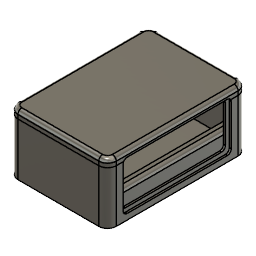
Modulo Servo (4 x6) (Autodesk Fusion 360 design; units mm, degrees)
Autodesk Fusion 360 part; units mm, degrees
sketch "Esboço1" plane through (0, 0, 0) normal (0, 0, 1) x (1, 0, 0)
  line L0 (0, 0) -> (22, 0)
  line L1 (0, 0) -> (0, 10)
  line L2 (0, 10) -> (4, 10)
  line L3 (4, 10) -> (4, 8)
  line L4 (4, 8) -> (2, 8)
  line L5 (2, 8) -> (2, 6)
  line L6 (2, 6) -> (4, 6)
  line L7 (4, 6) -> (4, 4)
  line L8 (4, 4) -> (2, 4)
  line L9 (2, 4) -> (2, 2)
  line L10 (2, 2) -> (22, 2)
  line L11 (22, 2) -> (22, 0)
  line L12 (40, 6) -> (40, 4)
  line L13 (40, 10) -> (40, 8)
  line L14 (44, 10) -> (40, 10)
  line L15 (42, 4) -> (42, 2)
  line L16 (22, 2) -> (22, 0)
  line L17 (42, 2) -> (22, 2)
  line L18 (42, 6) -> (40, 6)
  line L19 (44, 0) -> (22, 0)
  line L20 (40, 8) -> (42, 8)
  line L21 (42, 8) -> (42, 6)
  line L22 (44, 0) -> (44, 10)
  line L23 (40, 4) -> (42, 4)
  point P0 (44, 0)
  dimension "d2" = 10
  dimension "d3" = 4
  dimension "d4" = 2
  dimension "d5" = 2
  dimension "d6" = 2
  dimension "d7" = 2
  dimension "d8" = 2
  dimension "d9" = 2
  dimension "d10" = 2
  dimension "d11" = 20
  constraint coincident L0.start L1.start
  constraint horizontal L0
  constraint perpendicular L0 L1
  constraint perpendicular L1 L2
  constraint perpendicular L2 L3
  constraint perpendicular L1 L4
  constraint perpendicular L4 L5
  constraint perpendicular L5 L6
  constraint perpendicular L6 L7
  constraint perpendicular L7 L8
  constraint perpendicular L0 L9
  constraint perpendicular L9 L10
  constraint symmetric L0.start L11 L19.start
  constraint symmetric L0.start L11 P0
  constraint symmetric L1.end L11 L14.start
  constraint symmetric L2.end L11 L13.start
  constraint symmetric L3.end L11 L13.end
  constraint symmetric L4.end L11 L20.end
  constraint symmetric L5.end L11 L18.start
  constraint symmetric L6.end L11 L12.start
  constraint symmetric L7.end L11 L12.end
  constraint symmetric L8.end L11 L15.start
  constraint symmetric L9.end L11 L15.end
  constraint symmetric L10.end L11 L16.start
  constraint symmetric L0.end L11 L16.end
  measures "d2" distance of L0.start L1.end
  measures "d3" distance of L1.end L2.end
  measures "d4" distance of L2.end L3.end
  measures "d5" distance of L3.end L4.end
  measures "d6" distance of L4.end L5.end
  measures "d7" distance of L5.end L6.end
  measures "d8" distance of L6.end L7.end
  measures "d9" distance of L7.end L8.end
  measures "d10" distance of L8.end L9.end
  measures "d11" distance of L9.end L10.end
sketch "Esboço2" plane through (0, 0, 0) normal (0, 0, 1) x (1, 0, 0)
extrude "Extrusão1" add sketch "Esboço1" along normal blind 65 makes body 1
fillet "Arredondamento1" radius 2 2 edges at (0, 10, 32.5) (44, 10, 32.5) on bodies 1
sketch "Esboço3" plane through (0, 0, 65) normal (0, 0, 1) x (1, 0, 0)
  arc A0 (44, 8) -> (42, 10) centre (42, 8) ccw
  line L0 (42, 10) -> (40, 10)
  line L1 (40, 10) -> (40, 8)
  line L2 (40, 8) -> (42, 8)
  line L3 (42, 8) -> (42, 6)
  line L4 (42, 6) -> (40, 6)
  line L5 (40, 6) -> (40, 4)
  line L6 (40, 4) -> (42, 4)
  line L7 (42, 4) -> (42, 2)
  line L8 (42, 2) -> (2, 2)
  line L9 (2, 2) -> (2, 4)
  line L10 (2, 4) -> (4, 4)
  line L11 (4, 4) -> (4, 6)
  line L12 (4, 6) -> (2, 6)
  line L13 (2, 6) -> (2, 8)
  line L14 (2, 8) -> (4, 8)
  line L15 (4, 8) -> (4, 10)
  line L16 (4, 10) -> (2, 10)
  arc A1 (2, 10) -> (0, 8) centre (2, 8) ccw
  line L17 (0, 8) -> (0, 0)
  line L18 (0, 0) -> (44, 0)
  line L19 (44, 0) -> (44, 8)
  line L20 (2, 8) -> (4, 8)
  line L21 (4, 8) -> (4, 6)
  line L22 (4, 6) -> (2, 6)
  line L23 (2, 6) -> (2, 8)
  line L24 (40, 8) -> (42, 8)
  line L25 (42, 8) -> (42, 6)
  line L26 (42, 6) -> (40, 6)
  line L27 (40, 6) -> (40, 8)
  constraint horizontal L20
  constraint vertical L21
  constraint horizontal L22
  constraint vertical L23
  constraint coincident L11.end L12.start
  constraint coincident L13.end L14.start
  constraint horizontal L24
  constraint vertical L25
  constraint horizontal L26
  constraint vertical L27
  constraint coincident L3.end L4.start
  constraint coincident L1.end L2.start
sketch "Esboço5" plane through (0, 0, 0) normal (0, -1, 0) x (1, 0, 0)
  line L0 (0, 0) -> (44, 0)
  line L1 (44, 0) -> (44, 65)
  line L2 (44, 65) -> (0, 65)
  line L3 (0, 65) -> (0, 0)
  line L4 (0, 0) -> (0, 32.5)
  line L5 (0, 32.5) -> (22, 32.5)
  line L6 (46.5, 67.5) -> (-2.5, 67.5)
  line L7 (-2.5, 67.5) -> (-2.5, -2.5)
  line L8 (-2.5, -2.5) -> (46.5, -2.5)
  line L9 (46.5, -2.5) -> (46.5, 67.5)
  line L10 (46.5, 67.5) -> (-2.5, -2.5) construction
  line L11 (-2.5, 67.5) -> (46.5, -2.5) construction
  line L12 (45, 66) -> (-1, 66)
  line L13 (-1, 66) -> (-1, -1)
  line L14 (-1, -1) -> (45, -1)
  line L15 (45, -1) -> (45, 66)
  line L16 (45, 66) -> (-1, -1) construction
  line L17 (-1, 66) -> (45, -1) construction
  point P0 (22, 32.5)
  point P1 (22, 32.5)
  dimension "d33" = 32.5
  dimension "d34" = 22
  dimension "d35" = 70
  dimension "d36" = 49
  dimension "d37" = 46
  dimension "d38" = 67
  constraint coincident L0.start L3.end
  constraint perpendicular L2 L4
  constraint perpendicular L4 L5
  constraint horizontal L6
  constraint perpendicular L6 L7
  constraint parallel L6 L8
  constraint parallel L7 L9
  constraint coincident L10 P1
  constraint coincident L11 P1
  constraint coincident P1 P0
  constraint horizontal L12
  constraint perpendicular L12 L13
  constraint parallel L12 L14
  constraint parallel L13 L15
  constraint coincident L16 P1
  constraint coincident L17 P1
  measures "d33" distance of L0.start L4.end
  measures "d34" distance of L4.end P1
  measures "d35" distance of L6.end L7.end
  measures "d36" distance of L7.end L8.end
  measures "d37" distance of L13.end L14.end
  measures "d38" distance of L12.end L13.end
copy_body "Corpo -> Componente1" bodies 1 removing the originals makes body 2 in component "Placa 4x6"
sketch "Esboço7" plane through (0, 0, 0) normal (0, -1, 0) x (1, 0, 0)
  line L0 (0, 0) -> (44, 0)
  line L1 (44, 0) -> (44, 65)
  line L2 (44, 65) -> (0, 65)
  line L3 (0, 65) -> (0, 0)
  line L4 (0, 0) -> (0, 32.5)
  line L5 (0, 32.5) -> (22, 32.5)
  line L6 (44.75, -0.75) -> (-0.75, -0.75)
  line L7 (-0.75, -0.75) -> (-0.75, 65.75)
  line L8 (-0.75, 65.75) -> (44.75, 65.75)
  line L9 (44.75, 65.75) -> (44.75, -0.75)
  line L10 (44.75, -0.75) -> (-0.75, 65.75) construction
  line L11 (-0.75, -0.75) -> (44.75, 65.75) construction
  line L12 (42.75, 67.75) -> (1.25, 67.75)
  line L13 (-2.75, 63.75) -> (-2.75, 1.25)
  line L14 (1.25, -2.75) -> (42.75, -2.75)
  line L15 (46.75, 1.25) -> (46.75, 63.75)
  line L16 (46.75, 67.75) -> (-2.75, -2.75) construction
  line L17 (-2.75, 67.75) -> (46.75, -2.75) construction
  arc A0 (1.25, 67.75) -> (-2.75, 63.75) centre (1.25, 63.75) ccw
  arc A1 (46.75, 63.75) -> (42.75, 67.75) centre (42.75, 63.75) ccw
  arc A2 (42.75, -2.75) -> (46.75, 1.25) centre (42.75, 1.25) ccw
  arc A3 (-2.75, 1.25) -> (1.25, -2.75) centre (1.25, 1.25) ccw
  point P0 (22, 32.5)
  point P1 (22, 32.5)
  dimension "d45" = 32.5
  dimension "d46" = 22
  dimension "d47" = 66.5
  dimension "d48" = 45.5
  dimension "d49" = 49.5
  dimension "d50" = 70.5
  dimension "d54" = 4
  constraint coincident L0.start L3.end
  constraint perpendicular L0 L4
  constraint perpendicular L4 L5
  constraint horizontal L6
  constraint perpendicular L6 L7
  constraint parallel L6 L8
  constraint parallel L7 L9
  constraint coincident L10 P1
  constraint coincident L11 P1
  constraint coincident P1 P0
  constraint horizontal L12
  constraint perpendicular L12 L13
  constraint parallel L12 L14
  constraint parallel L13 L15
  constraint coincident L16 P1
  constraint coincident L17 P1
  constraint coincident L17.start L13
  constraint coincident L17.start L12
  constraint tangent L13 A0
  constraint tangent L12 A0
  constraint coincident L16.start L12
  constraint coincident L16.start L15
  constraint tangent L12 A1
  constraint tangent L15 A1
  constraint equal A0 A1
  constraint coincident L17.end L14
  constraint coincident L17.end L15
  constraint tangent L14 A2
  constraint tangent L15 A2
  constraint equal A0 A2
  constraint coincident L16.end L14
  constraint coincident L16.end L13
  constraint tangent L14 A3
  constraint tangent L13 A3
  constraint equal A0 A3
  measures "d45" distance of L0.start L4.end
  measures "d46" distance of L4.end P1
  measures "d47" distance of L6.end L7.end
  measures "d48" distance of L7.end L8.end
  measures "d49" distance of L16.end L17.end
  measures "d50" distance of L17.start L16.end
  measures "d54" radius of A0
extrude "Extrusão8" add sketch "Esboço7" against normal blind 25 thin wall 1 centred separate body contours L12 L13 L14 L15 A0 A1 A2 A3 makes body 3
copy_body "Corpo -> Componente2" bodies 3 removing the originals makes body 4 in component "Suporte Placa (1)"
extrude "Extrusão1'" add sketch "Esboço7" along normal blind 2 contours L0 L1 L2 L3 L4 | L6 L7 L8 L9 | L12 L13 L14 L15 A0 A1 A2 A3 bodies 4 in component "Suporte Placa (1)"
sketch "Esboço1 (2)" plane through (0, 25, 0) normal (0, 1, 0) x (-1, 0, 0) in component "Suporte Placa (1)"
  arc A0 (2.25, 63.75) -> (1.25, 66.1995) centre (-1.25, 63.75) ccw
  line L0 (2.25, 63.75) -> (2.25, 1.25)
  arc A1 (1.25, -1.1995) -> (2.25, 1.25) centre (-1.25, 1.25) ccw
  line L1 (1.25, -1.1995) -> (1.25, 66.1995)
  arc A2 (-42.75, 67.25) -> (-45.1995, 66.25) centre (-42.75, 63.75) ccw
  line L2 (-42.75, 67.25) -> (-1.25, 67.25)
  arc A3 (1.1995, 66.25) -> (-1.25, 67.25) centre (-1.25, 63.75) ccw
  line L3 (1.1995, 66.25) -> (-45.1995, 66.25)
  arc A4 (-1.25, -2.25) -> (1.1995, -1.25) centre (-1.25, 1.25) ccw
  line L4 (-1.25, -2.25) -> (-42.75, -2.25)
  arc A5 (-45.1995, -1.25) -> (-42.75, -2.25) centre (-42.75, 1.25) ccw
  line L5 (-45.1995, -1.25) -> (1.1995, -1.25)
  arc A6 (-46.25, 1.25) -> (-45.25, -1.1995) centre (-42.75, 1.25) ccw
  line L6 (-46.25, 1.25) -> (-46.25, 63.75)
  arc A7 (-45.25, 66.1995) -> (-46.25, 63.75) centre (-42.75, 63.75) ccw
  line L7 (-45.25, 66.1995) -> (-45.25, -1.1995)
  line L8 (-44.25, 65.25) -> (0.25, 65.25)
  line L9 (0.25, 65.25) -> (0.25, -0.25)
  line L10 (0.25, -0.25) -> (-44.25, -0.25)
  line L11 (-44.25, -0.25) -> (-44.25, 65.25)
  arc A8 (-1.25, -3.25) -> (3.25, 1.25) centre (-1.25, 1.25) ccw
  line L12 (3.25, 1.25) -> (3.25, 63.75)
  arc A9 (3.25, 63.75) -> (-1.25, 68.25) centre (-1.25, 63.75) ccw
  line L13 (-1.25, 68.25) -> (-42.75, 68.25)
  arc A10 (-42.75, 68.25) -> (-47.25, 63.75) centre (-42.75, 63.75) ccw
  line L14 (-47.25, 63.75) -> (-47.25, 1.25)
  line L15 (-42.75, -3.25) -> (-1.25, -3.25)
  line L16 (0.25, -0.25) -> (0.25, 1.75)
  line L17 (0.25, -0.25) -> (-1.75, -0.25)
  line L18 (-1.75, -0.25) -> (-1.75, -3.25)
  line L19 (0.25, 1.75) -> (3.25, 1.75)
  line L20 (-42.25, -3.25) -> (-42.75, -3.25)
  line L21 (-47.25, 1.25) -> (-47.25, 1.75)
  line L22 (-22, -3.25) -> (-22, 32.5)
  line L23 (-22, 32.5) -> (3.25, 32.5)
  arc A11 (3.25, 63.75) -> (-1.25, 68.25) centre (-1.25, 63.75) ccw
  line L24 (-1.75, 65.25) -> (-1.75, 68.25)
  line L25 (0.25, 65.25) -> (-1.75, 65.25)
  line L26 (0.25, 63.25) -> (3.25, 63.25)
  line L27 (0.25, 63.25) -> (0.25, 65.25)
  line L28 (-44.25, 1.75) -> (-47.25, 1.75)
  line L29 (-44.25, -0.25) -> (-44.25, 1.75)
  line L30 (-44.25, -0.25) -> (-42.25, -0.25)
  line L31 (-42.25, -0.25) -> (-42.25, -3.25)
  arc A12 (-47.25, 1.25) -> (-42.75, -3.25) centre (-42.75, 1.25) ccw
  line L32 (-44.25, 63.25) -> (-47.25, 63.25)
  line L33 (-44.25, 63.25) -> (-44.25, 65.25)
  line L34 (-44.25, 65.25) -> (-42.25, 65.25)
  line L35 (-42.25, 65.25) -> (-42.25, 68.25)
  arc A13 (-42.75, 68.25) -> (-47.25, 63.75) centre (-42.75, 63.75) ccw
  dimension "d57" = 2
  dimension "d58" = 2
  dimension "d59" = 35.75
  constraint coincident L9.end L10.start
  constraint perpendicular L10 L16
  constraint perpendicular L16 L17
  constraint coincident L15 L18.end
  constraint perpendicular L15 L18
  constraint coincident L12 L19.end
  constraint perpendicular L12 L19
  constraint midpoint L15 L22.start
  constraint perpendicular L10 L22
  constraint midpoint L12 L23.end
  constraint symmetric A8.start L23 A9.end
  constraint symmetric A8.end L23 L12.end
  constraint symmetric A8 L23 A11
  constraint symmetric L16.end L23 L26.start
  constraint symmetric L9.end L23 L8.end
  constraint symmetric L17.end L23 L24.start
  constraint symmetric L18.end L23 L24.end
  constraint symmetric L19.end L23 L26.end
  constraint coincident L8.end L9.start
  constraint symmetric A8.start L22 L15.start
  constraint symmetric A8.end L22 L14.end
  constraint symmetric A8 L22 A12
  constraint symmetric L9.end L22 L10.end
  constraint symmetric L16.end L22 L28.start
  constraint symmetric L17.end L22 L30.end
  constraint symmetric L18.end L22 L20.start
  constraint symmetric L19.end L22 L21.end
  constraint symmetric L22 A9.end L13.end
  constraint symmetric L22 L12.end A10.end
  constraint symmetric L22 A11 A13
  constraint symmetric L22 L24.start L34.end
  constraint symmetric L22 L24.end L35.end
  constraint symmetric L22 L8.end L8.start
  constraint symmetric L22 L26.start L32.start
  constraint symmetric L22 L26.end L32.end
  measures "d57" distance of L9.end L16.end
  measures "d58" distance of L9.end L17.end
  measures "d59" distance of L22.start L22.end
extrude "Extrusão2" add sketch "Esboço1 (2)" against normal blind 25 contours A0 L0 L1 L26 | L0 A1 L1 L19 | L2 A3 L3 L24 | A2 L2 L3 L35 | A4 L4 L5 L18 | L4 A5 L5 L31 | L6 A7 L7 L32 | A6 L6 L7 L28 bodies 4 in component "Suporte Placa (1)"
extrude "Extrusão3" cut sketch "Esboço1 (2)" against normal blind 1.5 contours A0 L0 L1 L26 | L0 A1 L1 L19 | L2 A3 L3 L24 | A2 L2 L3 L35 | A4 L4 L5 L18 | L4 A5 L5 L31 | L6 A7 L7 L32 | A6 L6 L7 L28 bodies 4 in component "Suporte Placa (1)"
extrude "Extrusão4" add 1 faces at (30.25, -2, 22.0833) along direction (0, 1, 0) blind 2 thin wall 1 centred on bodies 4 bodies 4 in component "Suporte Placa (1)"
ref_plane "Plano de trabalho1" through (22, 25, 32.5) normal (0, 1, 0) x (-1, 0, 0) in component "Suporte Placa (1)"
sketch "Esboço3 (2)" plane through (0, 25, 0) normal (0, 1, 0) x (1, 0, 0) in component "Suporte Placa (1)"
extrude "Extrusão7" add 1 faces at (-0.9167, 25, 21.5833) along direction (0, 1, 0) blind 2 separate body on bodies 4 makes body 5 in component "Suporte Placa (1)"
copy_body "CutPasteBodies1" bodies 5 removing the originals makes body 6 in component "Tampa"
sketch "Esboço1 (3)" plane through (0, 27, 0) normal (0, 1, 0) x (-1, 0, 0) in component "Tampa"
  line L0 (-44.25, -0.25) -> (-44.25, 65.25)
  line L1 (-44.25, 65.25) -> (0.25, 65.25)
  line L2 (0.25, 65.25) -> (0.25, -0.25)
  line L3 (0.25, -0.25) -> (-44.25, -0.25)
  line L4 (-45.25, 66.1995) -> (-45.25, -1.1995)
  arc A0 (-46.25, 1.25) -> (-45.25, -1.1995) centre (-42.75, 1.25) ccw
  line L5 (-46.25, 1.25) -> (-46.25, 63.75)
  line L6 (-47.25, 63.75) -> (-47.25, 1.25)
  arc A1 (-47.25, 1.25) -> (-42.75, -3.25) centre (-42.75, 1.25) ccw
  line L7 (-42.75, -3.25) -> (-1.25, -3.25)
  arc A2 (-1.25, -3.25) -> (3.25, 1.25) centre (-1.25, 1.25) ccw
  line L8 (3.25, 1.25) -> (3.25, 63.75)
  arc A3 (3.25, 63.75) -> (-1.25, 68.25) centre (-1.25, 63.75) ccw
  line L9 (-1.25, 68.25) -> (-42.75, 68.25)
  arc A4 (-42.75, 68.25) -> (-47.25, 63.75) centre (-42.75, 63.75) ccw
  arc A5 (-45.25, 66.1995) -> (-46.25, 63.75) centre (-42.75, 63.75) ccw
  line L10 (2.25, 63.75) -> (2.25, 1.25)
  arc A6 (1.25, -1.1995) -> (2.25, 1.25) centre (-1.25, 1.25) ccw
  line L11 (1.25, -1.1995) -> (1.25, 66.1995)
  arc A7 (2.25, 63.75) -> (1.25, 66.1995) centre (-1.25, 63.75) ccw
  line L12 (-42.75, 67.25) -> (-1.25, 67.25)
  arc A8 (1.1995, 66.25) -> (-1.25, 67.25) centre (-1.25, 63.75) ccw
  line L13 (1.1995, 66.25) -> (-45.1995, 66.25)
  arc A9 (-42.75, 67.25) -> (-45.1995, 66.25) centre (-42.75, 63.75) ccw
  line L14 (-1.25, -2.25) -> (-42.75, -2.25)
  arc A10 (-45.1995, -1.25) -> (-42.75, -2.25) centre (-42.75, 1.25) ccw
  line L15 (-45.1995, -1.25) -> (1.1995, -1.25)
  arc A11 (-1.25, -2.25) -> (1.1995, -1.25) centre (-1.25, 1.25) ccw
  line L16 (-47.25, 60.5) -> (-47.25, 63.75)
  constraint coincident L6.start A4.end
extrude "Extrusão1''" add sketch "Esboço1 (3)" along normal blind 2 contours L0 L1 L2 L3 | L4 A0 L5 A5 | L6 A1 L7 A2 L8 A3 L9 A4 L16 | L10 A6 L11 A7 | L12 A8 L13 A9 | L14 A10 L15 A11 bodies 6 in component "Tampa"
fillet "Arredondamento1'" radius 2 8 edges at (47.25, 29, 32.5) (45.932, 29, -1.932) (22, 29, -3.25) (-1.932, 29, -1.932) (-3.25, 29, 32.5) (-1.932, 29, 66.932) (22, 29, 68.25) (45.932, 29, 66.932) on bodies 6 in component "Tampa"
extrude "Extrusão2'" add sketch "Esboço1 (2)" along normal blind 3 and the other way blind 2 contours A0 L0 L1 L26 | L0 A1 L1 L19 | L2 A3 L3 L24 | A2 L2 L3 L35 | A4 L4 L5 L18 | L4 A5 L5 L31 | L6 A7 L7 L32 | A6 L6 L7 L28 bodies 6 in component "Tampa"
sketch "Esboço8" plane through (47.25, 0, 0) normal (1, 0, 0) x (0, 0, -1)
  line L0 (-1.25, -2) -> (-1.25, 25)
  line L1 (-1.25, 25) -> (-63.75, 25)
  line L2 (-63.75, 25) -> (-63.75, -2)
  line L3 (-63.75, -2) -> (-1.25, -2)
  line L4 (-63.75, -2) -> (-32.5, -2)
  line L5 (-32.5, -2) -> (-32.5, 13.5)
  line L6 (-6.75, 26) -> (-58.25, 26)
  line L7 (-60.25, 24) -> (-60.25, 3)
  line L8 (-58.25, 1) -> (-6.75, 1)
  line L9 (-4.75, 3) -> (-4.75, 24)
  line L10 (-4.75, 26) -> (-60.25, 1) construction
  line L11 (-60.25, 26) -> (-4.75, 1) construction
  arc A0 (-58.25, 26) -> (-60.25, 24) centre (-58.25, 24) ccw
  arc A1 (-60.25, 3) -> (-58.25, 1) centre (-58.25, 3) ccw
  arc A2 (-6.75, 1) -> (-4.75, 3) centre (-6.75, 3) ccw
  arc A3 (-4.75, 24) -> (-6.75, 26) centre (-6.75, 24) ccw
  line L12 (-7.75, 25) -> (-57.25, 25)
  line L13 (-59.25, 23) -> (-59.25, 4)
  line L14 (-57.25, 2) -> (-7.75, 2)
  line L15 (-5.75, 4) -> (-5.75, 23)
  line L16 (-5.75, 25) -> (-59.25, 2) construction
  line L17 (-59.25, 25) -> (-5.75, 2) construction
  arc A4 (-57.25, 25) -> (-59.25, 23) centre (-57.25, 23) ccw
  arc A5 (-59.25, 4) -> (-57.25, 2) centre (-57.25, 4) ccw
  arc A6 (-7.75, 2) -> (-5.75, 4) centre (-7.75, 4) ccw
  arc A7 (-5.75, 23) -> (-7.75, 25) centre (-7.75, 23) ccw
  point P0 (-32.5, 13.5)
  point P1 (-32.5, 13.5)
  dimension "d99" = 15.5
  dimension "d100" = 55.5
  dimension "d101" = 25
  dimension "d102" = 2
  dimension "d103" = 53.5
  dimension "d104" = 23
  dimension "d105" = 2
  constraint coincident L2.end L3.start
  constraint midpoint L3 L4.end
  constraint perpendicular L3 L5
  constraint horizontal L6
  constraint perpendicular L6 L7
  constraint parallel L6 L8
  constraint parallel L7 L9
  constraint coincident L10 P1
  constraint coincident L11 P1
  constraint coincident P1 P0
  constraint coincident L11.start L6
  constraint coincident L11.start L7
  constraint tangent L6 A0
  constraint tangent L7 A0
  constraint coincident L10.end L7
  constraint coincident L10.end L8
  constraint tangent L7 A1
  constraint tangent L8 A1
  constraint equal A0 A1
  constraint coincident L11.end L9
  constraint coincident L11.end L8
  constraint tangent L9 A2
  constraint tangent L8 A2
  constraint equal A0 A2
  constraint coincident L10.start L9
  constraint coincident L10.start L6
  constraint tangent L9 A3
  constraint tangent L6 A3
  constraint equal A0 A3
  constraint horizontal L12
  constraint perpendicular L12 L13
  constraint parallel L12 L14
  constraint parallel L13 L15
  constraint coincident L16 P1
  constraint coincident L17 P1
  constraint coincident L17.start L12
  constraint coincident L17.start L13
  constraint tangent L12 A4
  constraint tangent L13 A4
  constraint coincident L16.end L13
  constraint coincident L16.end L14
  constraint tangent L13 A5
  constraint tangent L14 A5
  constraint equal A4 A5
  constraint coincident L17.end L14
  constraint coincident L17.end L15
  constraint tangent L14 A6
  constraint tangent L15 A6
  constraint equal A4 A6
  constraint coincident L16.start L15
  constraint coincident L16.start L12
  constraint tangent L15 A7
  constraint tangent L12 A7
  constraint equal A4 A7
  measures "d100" distance of L10.end L11.end
  measures "d101" distance of L11.start L10.end
  measures "d102" radius of A0
  measures "d103" distance of L16.end L17.end
  measures "d104" distance of L17.start L16.end
  measures "d105" radius of A4
extrude "Extrusão9" cut sketch "Esboço8" against normal blind 3 contours L1 L12 L13 L14 L15 A4 A5 A6 A7 bodies 4 in component "Suporte Placa (1)"
extrude "Extrusão4'" [no effect] in component "Tampa"
extrude "Extrusão10" cut sketch "Esboço8" against normal blind 2 contours L1 L5 L8 L9 A2 A3 L14 L15 A6 A7 | L1 L6 A0 A3 L12 | L1 L5 L7 L8 A0 A1 L13 L14 A4 A5 | L1 L12 L13 L14 L15 A4 A5 A6 A7 bodies 4 in component "Suporte Placa (1)"
extrude "Extrusão5" cut sketch "Esboço8" against normal blind 2 contours L1 L5 L8 L9 A2 A3 L14 L15 A6 A7 | L1 L6 A0 A3 L12 | L1 L5 L7 L8 A0 A1 L13 L14 A4 A5 | L1 L12 L13 L14 L15 A4 A5 A6 A7 bodies 6 in component "Tampa"
component "Placa 4x6" placed x (1, 0, 0) y (0, 1, 0) z (0, 0, 1) at (0, 0, 0)
component "Suporte Placa (1)" placed x (1, 0, 0) y (0, 1, 0) z (0, 0, 1) at (0, 0, 0)
component "Tampa" placed x (1, 0, 0) y (0, 1, 0) z (0, 0, 1) at (0, 0, 0)
named bodies: "Placa 4x6"
